Autodesk Fusion 360 part; units mm, degrees
(part 2 of 2)
equation "d182 = abs(pitch / 2 - tongueWidth / 2)"
equation "d183 = abs(pitch - tongueLength / 2)"
equation "d184 = tongueWidth"
equation "d185 = tongueLength"
equation "d186 = -tongueDepth"
equation "d188 = boardThickness - tongueDepth"
equation "d190 = abs(pitch / 2 - tongueWidth / 2)"
equation "d191 = abs(pitch - 2 mm)"
equation "d192 = tongueWidth"
equation "d194 = tongueDepth"
equation "d196 = boardThickness - tongueDepth"
equation "d198 = ( abs(pitch / 2) ) - webCenterOffset"
equation "d199 = abs(pitch)"
equation "d200 = panelClearance"
equation "d201 = hookClearance + carrierThickness + tongueDepth"
equation "d203 = carrierZ + 2 mm"
equation "d205 = ( abs(pitch / 2 - 2.15 mm) ) - webCenterOffset"
equation "d206 = abs(pitch - 2.4 mm)"
equation "d211 = ( carrierZ + 2.2 mm ) * 1.0"
equation "d213 = ( abs(( pitch / 2 + ( 2.0 mm ) ) * 1) ) - webCenterOffset"
equation "d214 = abs(( pitch + ( 1.154701 mm ) ) * 1)"
equation "d215 = ( abs(( pitch / 2 + ( 0.0 mm ) ) * 1) ) - webCenterOffset"
equation "d216 = abs(( pitch + ( 2.309401 mm ) ) * 1)"
equation "d217 = ( abs(( pitch / 2 + ( -2.0 mm ) ) * 1) ) - webCenterOffset"
equation "d218 = abs(( pitch + ( -1.154701 mm ) ) * 1)"
equation "d219 = ( abs(( pitch / 2 + ( -0.0 mm ) ) * 1) ) - webCenterOffset"
equation "d220 = abs(( pitch + ( -2.309401 mm ) ) * 1)"
equation "d221 = ( 1.6 mm ) * 1.0"
equation "d223 = carrierZ + 2.2 mm"
equation "d225 = ( abs(pitch / 2) ) - webCenterOffset"
equation "d226 = abs(pitch)"
equation "d248 = ( abs(pitch / 2) ) - webCenterOffset"
equation "d249 = abs(pitch)"
equation "d251 = ( 3.8 mm - 2 mm ) / 2"
equation "d253 = 0.1 mm + ( 3.8 mm - 2 mm ) / 2"
equation "d255 = ( abs(pitch / 2) ) - webCenterOffset"
equation "d256 = abs(pitch)"
equation "d258 = 20 mm - ( 3.8 mm - 2 mm ) / 2"
equation "d262 = ( abs(pitch / 2 - ( 0.55 mm ) / 2) ) - webCenterOffset"
equation "d263 = abs(pitch - ( 3.8 mm * 0.6 ) / 2)"
equation "d265 = 3.8 mm * 0.6"
equation "d270 = ( abs(pitch / 2 - ( 3.8 mm * 0.6 ) / 2) ) - webCenterOffset"
equation "d271 = abs(pitch - ( 0.55 mm ) / 2)"
equation "d272 = 3.8 mm * 0.6"
equation "d276 = frameZ"
equation "d278 = abs(pitch / 2 - 2.9 mm)"
equation "d279 = abs(pitch - 11 mm - 5 mm - 1 mm)"
equation "d284 = frameZ"
equation "d286 = abs(pitch / 2 - 2.9 mm)"
equation "d287 = abs(pitch - 11 mm + 5 mm - 1 mm)"
equation "d292 = carrierZ"
equation "d294 = abs(pitch / 2)"
equation "d295 = abs(pitch - 11 mm)"
equation "d296 = carrierBore"
equation "d297 = carrierThickness"
equation "d299 = carrierZ"
equation "d301 = abs(pitch / 2)"
equation "d302 = abs(pitch - 11 mm)"
equation "d303 = carrierHeadPocket"
equation "d304 = ( carrierHeadPocket - carrierBore ) / 2"
equation "d306 = carrierZ + 0.1 mm"
equation "d308 = abs(pitch / 2)"
equation "d309 = abs(pitch - 11 mm)"
equation "d311 = ( 9.2 mm - 5 mm ) / 2"
equation "d313 = carrierZ + 0.1 mm + ( 9.2 mm - 5 mm ) / 2"
equation "d315 = abs(pitch / 2)"
equation "d316 = abs(pitch - 11 mm)"
equation "d318 = 12 mm - ( 9.2 mm - 5 mm ) / 2"
equation "d320 = carrierZ + 0.1 mm"
equation "d322 = abs(pitch / 2 - ( 0.55 mm ) / 2)"
equation "d323 = abs(pitch - 11 mm - ( 9.2 mm * 0.6 ) / 2)"
equation "d325 = 9.2 mm * 0.6"
equation "d328 = carrierZ + 0.1 mm"
equation "d330 = abs(pitch / 2 - ( 9.2 mm * 0.6 ) / 2)"
equation "d331 = abs(pitch - 11 mm - ( 0.55 mm ) / 2)"
equation "d332 = 9.2 mm * 0.6"
equation "d336 = frameZ + profileLip"
equation "d338 = abs(pitch / 2 - nutWidth / 2)"
equation "d339 = abs(pitch - 11 mm - nutLength / 2)"
equation "d340 = nutWidth"
equation "d341 = nutLength"
equation "d342 = nutThickness"
equation "d344 = frameZ + profileLip"
equation "d346 = abs(pitch / 2)"
equation "d347 = abs(pitch - 11 mm)"
equation "d349 = nutThickness"
equation "d351 = carrierZ + 4 mm"
equation "d353 = ( abs(pitch / 2 - 2.15 mm) ) - webCenterOffset"
equation "d354 = abs(pitch + 2.5 mm)"
equation "d359 = carrierZ + 4.8 mm"
equation "d361 = ( abs(pitch / 2 - 2.15 mm) ) - webCenterOffset"
equation "d362 = abs(pitch + 3 mm)"
equation "d367 = carrierZ + 4 mm"
equation "d369 = ( abs(pitch / 2 - 2.15 mm) ) - webCenterOffset"
equation "d370 = abs(pitch + 3 mm)"
equation "d375 = carrierZ + 4 mm"
equation "d377 = ( abs(pitch / 2 + 1.65 mm) ) - webCenterOffset"
equation "d378 = abs(pitch + 3 mm)"
equation "d383 = ( ( pitch / 2 - 1.65 mm ) * 1.0 ) - webCenterOffset"
equation "d385 = abs(( carrierZ + 4.2 mm ) * -1)"
equation "d386 = abs(( pitch + 3 mm ) * 1)"
equation "d387 = abs(( pitch + 4.6 mm ) * 1)"
equation "d388 = abs(( carrierZ + 2.8 mm ) * -1)"
equation "d389 = abs(( pitch + 3.8 mm ) * 1)"
equation "d390 = ( ( 3.3 mm ) * 1.0 ) - webCenterOffset"
equation "webCenterOffset = ( slotHeight - slotWidth ) ^ 2 / ( 4 * pitch )" comment "Equal-distance M2 station for standard staggered lattice; preserve support axis"
equation "pixelGap = 0.4 mm" comment "Same as v0.5 axial tile prototype; fit trial"
equation "pixelThickness = 1.2 mm" comment "Same as v0.5 axial tile prototype; fit trial"
equation "tileBack = 0.8 mm" comment "Same as v0.5 axial tile prototype; fit trial"
equation "snapInterference = 0.4 mm" comment "Same as v0.5 axial tile prototype; fit trial"
equation "d397 = -tileBack"
equation "d399 = abs(60 mm - 4.5 mm)"
equation "d400 = abs(-9.5 mm)"
equation "d403 = tileBack"
equation "d405 = abs(60 mm - 0.6 mm)"
equation "d406 = abs(-slotHeight / 2 + 0.2 mm)"
equation "d408 = slotHeight - 0.4 mm"
equation "d409 = boardThickness - 0.2 mm"
equation "d411 = ( -3 mm ) * 1.0"
equation "d413 = abs(( 60 mm + ( 0.8 mm ) * -1 ) * 1)"
equation "d414 = abs(( 60 mm + ( 2.2 mm ) * -1 ) * 1)"
equation "d415 = abs(( boardThickness - 0.2 mm ) * -1)"
equation "d416 = abs(( 60 mm + ( ( slotWidth + snapInterference ) / 2 ) * -1 ) * 1)"
equation "d417 = abs(( boardThickness + 0.5 mm ) * -1)"
equation "d418 = abs(( boardThickness + 0.9 mm ) * -1)"
equation "d419 = abs(( 60 mm + ( 1.6 mm ) * -1 ) * 1)"
equation "d420 = abs(( boardThickness + 2.1 mm ) * -1)"
equation "d421 = ( 6 mm ) * 1.0"
equation "d423 = ( -3 mm ) * 1.0"
equation "d425 = abs(( 60 mm + ( 0.8 mm ) * 1 ) * 1)"
equation "d426 = abs(( 60 mm + ( 2.2 mm ) * 1 ) * 1)"
equation "d427 = abs(( boardThickness - 0.2 mm ) * -1)"
equation "d428 = abs(( 60 mm + ( ( slotWidth + snapInterference ) / 2 ) * 1 ) * 1)"
equation "d429 = abs(( boardThickness + 0.5 mm ) * -1)"
equation "d430 = abs(( boardThickness + 0.9 mm ) * -1)"
equation "d431 = abs(( 60 mm + ( 1.6 mm ) * 1 ) * 1)"
equation "d432 = abs(( boardThickness + 2.1 mm ) * -1)"
equation "d433 = ( 6 mm ) * 1.0"
equation "d435 = -tileBack - pixelThickness"
equation "d437 = abs(60 mm - 5 mm + pixelGap / 2)"
equation "d438 = abs(-10 mm + pixelGap / 2)"
equation "d439 = 10 mm - pixelGap"
equation "d440 = 10 mm - pixelGap"
equation "d441 = pixelThickness"
equation "d443 = -tileBack - pixelThickness"
equation "d445 = abs(60 mm - 5 mm + pixelGap / 2)"
equation "d446 = abs(pixelGap / 2)"
equation "d447 = 10 mm - pixelGap"
equation "d448 = 10 mm - pixelGap"
equation "d449 = pixelThickness"
